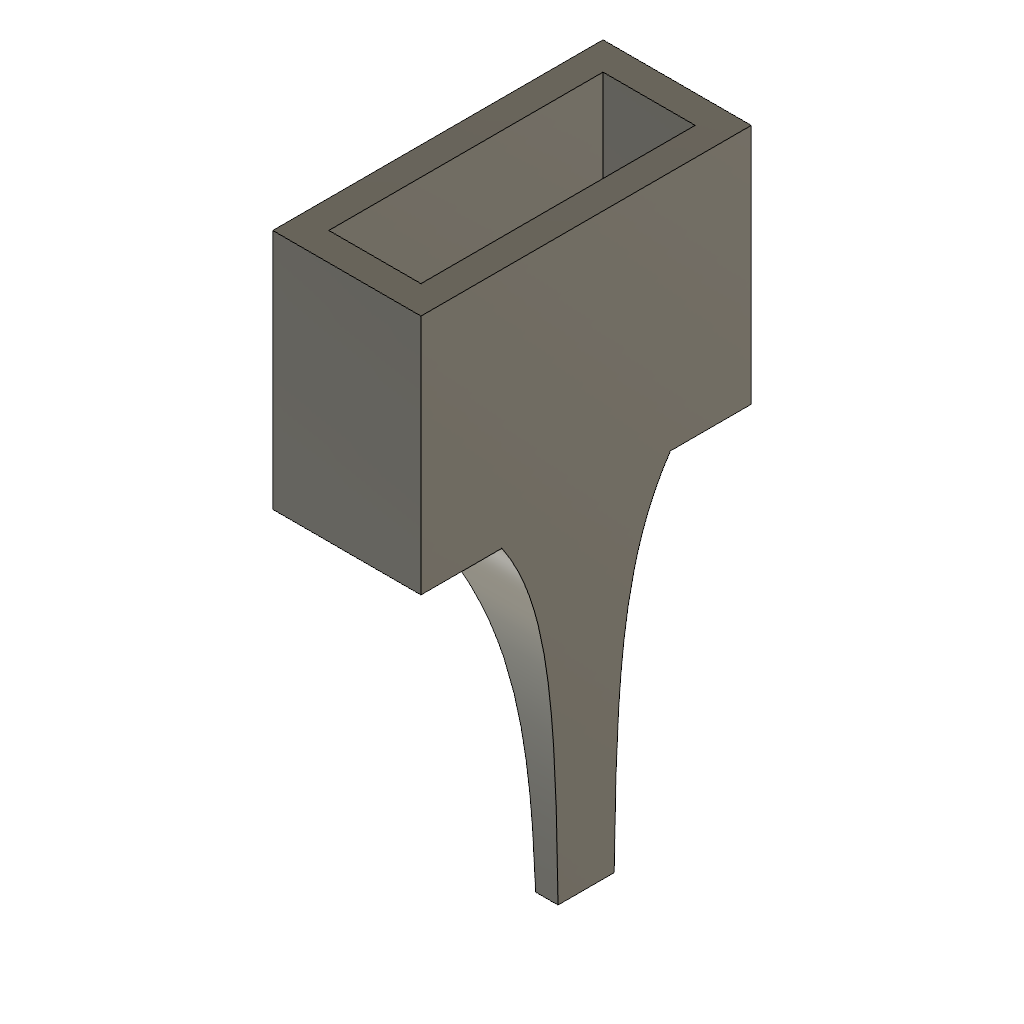
Gripper_R7_W15to5_L30_T2_C0p2 (Autodesk Fusion 360 design; units mm, degrees)
part number: 2026-10-26-02-16-46-155
Autodesk Fusion 360 part; units mm, degrees
sketch "01 - outside with 2.5 mm walls" plane through (0, 0, 0) normal (0, 0, 1) x (1, 0, 0)
  line L0 (-6.6, -14.7) -> (6.6, -14.7)
  line L1 (6.6, -14.7) -> (6.6, 14.7)
  line L2 (6.6, 14.7) -> (-6.6, 14.7)
  line L3 (-6.6, 14.7) -> (-6.6, -14.7)
  dimension "d12" = 13.2
  dimension "d13" = 29.4
  dimension "d14" = 6.6
  dimension "d15" = 14.7
  constraint horizontal L0
  constraint horizontal L2
  constraint vertical L1
  constraint vertical L3
  measures "d12" horizontal distance of L0.start L0.end
  measures "d13" vertical distance of L0.end L1.end
  measures "d14" horizontal distance of origin L0.start
  measures "d15" vertical distance of origin L0.start
extrude "02 - sleeve envelope with 2.5 mm closed base" add sketch "01 - outside with 2.5 mm walls" along normal blind 21.5
ref_plane "WorkPlane1" through (0, 0, 21.5) normal (0, 0, 1) x (1, 0, 0)
sketch "03 - finger pocket with fitting clearance" plane through (0, 0, 21.5) normal (0, 0, 1) x (1, 0, 0)
  line L0 (-4.1, -12.2) -> (4.1, -12.2)
  line L1 (4.1, -12.2) -> (4.1, 12.2)
  line L2 (4.1, 12.2) -> (-4.1, 12.2)
  line L3 (-4.1, 12.2) -> (-4.1, -12.2)
  dimension "d20" = 8.2
  dimension "d21" = 24.4
  dimension "d22" = 4.1
  dimension "d23" = 12.2
  constraint horizontal L0
  constraint horizontal L2
  constraint vertical L1
  constraint vertical L3
  measures "d20" horizontal distance of L0.start L0.end
  measures "d21" vertical distance of L0.end L1.end
  measures "d22" horizontal distance of origin L0.start
  measures "d23" vertical distance of origin L0.start
extrude "04 - open mouth and finger seating pocket" cut sketch "03 - finger pocket with fitting clearance" against normal blind 19
sketch "05 - exponential section 0" plane through (0, 0, 0) normal (0, 0, 1) x (1, 0, 0)
  line L0 (-6.6, -7.5) -> (6.6, -7.5)
  line L1 (6.6, -7.5) -> (6.6, 7.5)
  line L2 (6.6, 7.5) -> (-6.6, 7.5)
  line L3 (-6.6, 7.5) -> (-6.6, -7.5)
  dimension "d26" = 13.2
  dimension "d27" = 15
  dimension "d28" = 6.6
  dimension "d29" = 7.5
  constraint horizontal L0
  constraint horizontal L2
  constraint vertical L1
  constraint vertical L3
  measures "d26" horizontal distance of L0.start L0.end
  measures "d27" vertical distance of L0.end L1.end
  measures "d28" horizontal distance of origin L0.end
  measures "d29" vertical distance of origin L0.end
ref_plane "WorkPlane2" through (0, 0, -2.5) normal (0, 0, 1) x (1, 0, 0)
sketch "05 - exponential section 1" plane through (0, 0, -2.5) normal (0, 0, 1) x (1, 0, 0)
  line L0 (-3.3659, -6.0562) -> (6.6, -6.0562)
  line L1 (6.6, -6.0562) -> (6.6, 6.0562)
  line L2 (6.6, 6.0562) -> (-3.3659, 6.0562)
  line L3 (-3.3659, 6.0562) -> (-3.3659, -6.0562)
  dimension "d32" = 9.9659
  dimension "d33" = 12.1124
  dimension "d34" = 6.6
  dimension "d35" = 6.0562
  constraint horizontal L0
  constraint horizontal L2
  constraint vertical L1
  constraint vertical L3
  measures "d32" horizontal distance of L0.start L0.end
  measures "d33" vertical distance of L0.end L1.end
  measures "d34" horizontal distance of origin L0.end
  measures "d35" vertical distance of origin L0.end
ref_plane "WorkPlane3" through (0, 0, -5) normal (0, 0, 1) x (1, 0, 0)
sketch "05 - exponential section 2" plane through (0, 0, -5) normal (0, 0, 1) x (1, 0, 0)
  line L0 (-1.0486, -5.0217) -> (6.6, -5.0217)
  line L1 (6.6, -5.0217) -> (6.6, 5.0217)
  line L2 (6.6, 5.0217) -> (-1.0486, 5.0217)
  line L3 (-1.0486, 5.0217) -> (-1.0486, -5.0217)
  dimension "d38" = 7.6486
  dimension "d39" = 10.0434
  dimension "d40" = 6.6
  dimension "d41" = 5.0217
  constraint horizontal L0
  constraint horizontal L2
  constraint vertical L1
  constraint vertical L3
  measures "d38" horizontal distance of L0.start L0.end
  measures "d39" vertical distance of L0.end L1.end
  measures "d40" horizontal distance of origin L0.end
  measures "d41" vertical distance of origin L0.end
ref_plane "WorkPlane4" through (0, 0, -7.5) normal (0, 0, 1) x (1, 0, 0)
sketch "05 - exponential section 3" plane through (0, 0, -7.5) normal (0, 0, 1) x (1, 0, 0)
  line L0 (0.6118, -4.2804) -> (6.6, -4.2804)
  line L1 (6.6, -4.2804) -> (6.6, 4.2804)
  line L2 (6.6, 4.2804) -> (0.6118, 4.2804)
  line L3 (0.6118, 4.2804) -> (0.6118, -4.2804)
  dimension "d44" = 5.9882
  dimension "d45" = 8.5609
  dimension "d46" = 6.6
  dimension "d47" = 4.2804
  constraint horizontal L0
  constraint horizontal L2
  constraint vertical L1
  constraint vertical L3
  measures "d44" horizontal distance of L0.start L0.end
  measures "d45" vertical distance of L0.end L1.end
  measures "d46" horizontal distance of origin L0.end
  measures "d47" vertical distance of origin L0.end
ref_plane "WorkPlane5" through (0, 0, -10) normal (0, 0, 1) x (1, 0, 0)
sketch "05 - exponential section 4" plane through (0, 0, -10) normal (0, 0, 1) x (1, 0, 0)
  line L0 (1.8016, -3.7493) -> (6.6, -3.7493)
  line L1 (6.6, -3.7493) -> (6.6, 3.7493)
  line L2 (6.6, 3.7493) -> (1.8016, 3.7493)
  line L3 (1.8016, 3.7493) -> (1.8016, -3.7493)
  dimension "d50" = 4.7984
  dimension "d51" = 7.4986
  dimension "d52" = 6.6
  dimension "d53" = 3.7493
  constraint horizontal L0
  constraint horizontal L2
  constraint vertical L1
  constraint vertical L3
  measures "d50" horizontal distance of L0.start L0.end
  measures "d51" vertical distance of L0.end L1.end
  measures "d52" horizontal distance of origin L0.end
  measures "d53" vertical distance of origin L0.end
ref_plane "WorkPlane6" through (0, 0, -12.5) normal (0, 0, 1) x (1, 0, 0)
sketch "05 - exponential section 5" plane through (0, 0, -12.5) normal (0, 0, 1) x (1, 0, 0)
  line L0 (2.6541, -3.3687) -> (6.6, -3.3687)
  line L1 (6.6, -3.3687) -> (6.6, 3.3687)
  line L2 (6.6, 3.3687) -> (2.6541, 3.3687)
  line L3 (2.6541, 3.3687) -> (2.6541, -3.3687)
  dimension "d56" = 3.9459
  dimension "d57" = 6.7374
  dimension "d58" = 6.6
  dimension "d59" = 3.3687
  constraint horizontal L0
  constraint horizontal L2
  constraint vertical L1
  constraint vertical L3
  measures "d56" horizontal distance of L0.start L0.end
  measures "d57" vertical distance of L0.end L1.end
  measures "d58" horizontal distance of origin L0.end
  measures "d59" vertical distance of origin L0.end
ref_plane "WorkPlane7" through (0, 0, -15) normal (0, 0, 1) x (1, 0, 0)
sketch "05 - exponential section 6" plane through (0, 0, -15) normal (0, 0, 1) x (1, 0, 0)
  line L0 (3.2649, -3.096) -> (6.6, -3.096)
  line L1 (6.6, -3.096) -> (6.6, 3.096)
  line L2 (6.6, 3.096) -> (3.2649, 3.096)
  line L3 (3.2649, 3.096) -> (3.2649, -3.096)
  dimension "d62" = 3.3351
  dimension "d63" = 6.192
  dimension "d64" = 6.6
  dimension "d65" = 3.096
  constraint horizontal L0
  constraint horizontal L2
  constraint vertical L1
  constraint vertical L3
  measures "d62" horizontal distance of L0.start L0.end
  measures "d63" vertical distance of L0.end L1.end
  measures "d64" horizontal distance of origin L0.end
  measures "d65" vertical distance of origin L0.end
ref_plane "WorkPlane8" through (0, 0, -17.5) normal (0, 0, 1) x (1, 0, 0)
sketch "05 - exponential section 7" plane through (0, 0, -17.5) normal (0, 0, 1) x (1, 0, 0)
  line L0 (3.7026, -2.9006) -> (6.6, -2.9006)
  line L1 (6.6, -2.9006) -> (6.6, 2.9006)
  line L2 (6.6, 2.9006) -> (3.7026, 2.9006)
  line L3 (3.7026, 2.9006) -> (3.7026, -2.9006)
  dimension "d68" = 2.8974
  dimension "d69" = 5.8012
  dimension "d70" = 6.6
  dimension "d71" = 2.9006
  constraint horizontal L0
  constraint horizontal L2
  constraint vertical L1
  constraint vertical L3
  measures "d68" horizontal distance of L0.start L0.end
  measures "d69" vertical distance of L0.end L1.end
  measures "d70" horizontal distance of origin L0.end
  measures "d71" vertical distance of origin L0.end
ref_plane "WorkPlane9" through (0, 0, -20) normal (0, 0, 1) x (1, 0, 0)
sketch "05 - exponential section 8" plane through (0, 0, -20) normal (0, 0, 1) x (1, 0, 0)
  line L0 (4.0162, -2.7606) -> (6.6, -2.7606)
  line L1 (6.6, -2.7606) -> (6.6, 2.7606)
  line L2 (6.6, 2.7606) -> (4.0162, 2.7606)
  line L3 (4.0162, 2.7606) -> (4.0162, -2.7606)
  dimension "d74" = 2.5838
  dimension "d75" = 5.5212
  dimension "d76" = 6.6
  dimension "d77" = 2.7606
  constraint horizontal L0
  constraint horizontal L2
  constraint vertical L1
  constraint vertical L3
  measures "d74" horizontal distance of L0.start L0.end
  measures "d75" vertical distance of L0.end L1.end
  measures "d76" horizontal distance of origin L0.end
  measures "d77" vertical distance of origin L0.end
ref_plane "WorkPlane10" through (0, 0, -22.5) normal (0, 0, 1) x (1, 0, 0)
sketch "05 - exponential section 9" plane through (0, 0, -22.5) normal (0, 0, 1) x (1, 0, 0)
  line L0 (4.2409, -2.6603) -> (6.6, -2.6603)
  line L1 (6.6, -2.6603) -> (6.6, 2.6603)
  line L2 (6.6, 2.6603) -> (4.2409, 2.6603)
  line L3 (4.2409, 2.6603) -> (4.2409, -2.6603)
  dimension "d80" = 2.3591
  dimension "d81" = 5.3206
  dimension "d82" = 6.6
  dimension "d83" = 2.6603
  constraint horizontal L0
  constraint horizontal L2
  constraint vertical L1
  constraint vertical L3
  measures "d80" horizontal distance of L0.start L0.end
  measures "d81" vertical distance of L0.end L1.end
  measures "d82" horizontal distance of origin L0.end
  measures "d83" vertical distance of origin L0.end
ref_plane "WorkPlane11" through (0, 0, -25) normal (0, 0, 1) x (1, 0, 0)
sketch "05 - exponential section 10" plane through (0, 0, -25) normal (0, 0, 1) x (1, 0, 0)
  line L0 (4.402, -2.5884) -> (6.6, -2.5884)
  line L1 (6.6, -2.5884) -> (6.6, 2.5884)
  line L2 (6.6, 2.5884) -> (4.402, 2.5884)
  line L3 (4.402, 2.5884) -> (4.402, -2.5884)
  dimension "d86" = 2.198
  dimension "d87" = 5.1768
  dimension "d88" = 6.6
  dimension "d89" = 2.5884
  constraint horizontal L0
  constraint horizontal L2
  constraint vertical L1
  constraint vertical L3
  measures "d86" horizontal distance of L0.start L0.end
  measures "d87" vertical distance of L0.end L1.end
  measures "d88" horizontal distance of origin L0.end
  measures "d89" vertical distance of origin L0.end
ref_plane "WorkPlane12" through (0, 0, -27.5) normal (0, 0, 1) x (1, 0, 0)
sketch "05 - exponential section 11" plane through (0, 0, -27.5) normal (0, 0, 1) x (1, 0, 0)
  line L0 (4.5173, -2.5369) -> (6.6, -2.5369)
  line L1 (6.6, -2.5369) -> (6.6, 2.5369)
  line L2 (6.6, 2.5369) -> (4.5173, 2.5369)
  line L3 (4.5173, 2.5369) -> (4.5173, -2.5369)
  dimension "d92" = 2.0827
  dimension "d93" = 5.0738
  dimension "d94" = 6.6
  dimension "d95" = 2.5369
  constraint horizontal L0
  constraint horizontal L2
  constraint vertical L1
  constraint vertical L3
  measures "d92" horizontal distance of L0.start L0.end
  measures "d93" vertical distance of L0.end L1.end
  measures "d94" horizontal distance of origin L0.end
  measures "d95" vertical distance of origin L0.end
ref_plane "WorkPlane13" through (0, 0, -30) normal (0, 0, 1) x (1, 0, 0)
sketch "05 - exponential section 12" plane through (0, 0, -30) normal (0, 0, 1) x (1, 0, 0)
  line L0 (4.6, -2.5) -> (6.6, -2.5)
  line L1 (6.6, -2.5) -> (6.6, 2.5)
  line L2 (6.6, 2.5) -> (4.6, 2.5)
  line L3 (4.6, 2.5) -> (4.6, -2.5)
  dimension "d98" = 2
  dimension "d99" = 5
  dimension "d100" = 6.6
  dimension "d101" = 2.5
  constraint horizontal L0
  constraint horizontal L2
  constraint vertical L1
  constraint vertical L3
  measures "d98" horizontal distance of L0.start L0.end
  measures "d99" vertical distance of L0.end L1.end
  measures "d100" horizontal distance of origin L0.end
  measures "d101" vertical distance of origin L0.end
loft "06 - smooth exponential taper, aligned with +X sleeve wall" add profiles "05 - exponential section 0", "05 - exponential section 1", "05 - exponential section 2", "05 - exponential section 3", "05 - exponential section 4", "05 - exponential section 5", "05 - exponential section 6", "05 - exponential section 7", "05 - exponential section 8", "05 - exponential section 9", "05 - exponential section 10", "05 - exponential section 11", "05 - exponential section 12" section 1 section 2 section 3 section 4 section 5 section 6 section 7 section 8 section 9 section 10 section 11 section 12 section 13
equation "finger_width = 7.8 mm" comment "Measured finger width"
equation "finger_length = 24 mm" comment "Long edge of sleeve opening"
equation "finger_height = 19 mm" comment "Pocket depth along insertion axis"
equation "wall = 2.5 mm" comment "Sleeve side wall thickness"
equation "sleeve_height = finger_height + wall" comment "Pocket plus closed base thickness"
equation "blade_thickness = 2 mm" comment "Thickness at the gripping tip"
equation "blade_length = 30 mm" comment "Gripping finger length beyond the sleeve base"
equation "blade_width = 15 mm" comment "Gripping finger width at sleeve"
equation "blade_tip_width = 5 mm" comment "Gripping finger width at tip"
equation "fit_clearance = 0.2 mm" comment "ASSUMPTION: clearance on EACH side; test print to confirm fit"
equation "pocket_depth = finger_height" comment "Open recess depth to fit the existing finger"
equation "d12 = finger_width + 2 * fit_clearance + 2 * wall"
equation "d13 = finger_length + 2 * fit_clearance + 2 * wall"
equation "d14 = ( finger_width + 2 * fit_clearance + 2 * wall ) / 2"
equation "d15 = ( finger_length + 2 * fit_clearance + 2 * wall ) / 2"
equation "d16 = sleeve_height"
equation "d18 = sleeve_height"
equation "d20 = finger_width + 2 * fit_clearance"
equation "d21 = finger_length + 2 * fit_clearance"
equation "d22 = ( finger_width + 2 * fit_clearance ) / 2"
equation "d23 = ( finger_length + 2 * fit_clearance ) / 2"
equation "d24 = -( pocket_depth )"
equation "d26 = blade_thickness + ( ( finger_width + 2 * fit_clearance + 2 * wall ) - blade_thickness ) * 1.0"
equation "d27 = blade_tip_width + ( blade_width - blade_tip_width ) * 1.0"
equation "d28 = ( finger_width + 2 * fit_clearance + 2 * wall ) / 2"
equation "d29 = ( blade_tip_width + ( blade_width - blade_tip_width ) * 1.0 ) / 2"
equation "d30 = -blade_length * 0.08333333333333333"
equation "d32 = blade_thickness + ( ( finger_width + 2 * fit_clearance + 2 * wall ) - blade_thickness ) * 0.7112425330833178"
equation "d33 = blade_tip_width + ( blade_width - blade_tip_width ) * 0.7112425330833178"
equation "d34 = ( finger_width + 2 * fit_clearance + 2 * wall ) / 2"
equation "d35 = ( blade_tip_width + ( blade_width - blade_tip_width ) * 0.7112425330833178 ) / 2"
equation "d36 = -blade_length * 0.16666666666666666"
equation "d38 = blade_thickness + ( ( finger_width + 2 * fit_clearance + 2 * wall ) - blade_thickness ) * 0.5043387668755398"
equation "d39 = blade_tip_width + ( blade_width - blade_tip_width ) * 0.5043387668755398"
equation "d40 = ( finger_width + 2 * fit_clearance + 2 * wall ) / 2"
equation "d41 = ( blade_tip_width + ( blade_width - blade_tip_width ) * 0.5043387668755398 ) / 2"
equation "d42 = -blade_length * 0.25"
equation "d44 = blade_thickness + ( ( finger_width + 2 * fit_clearance + 2 * wall ) - blade_thickness ) * 0.3560857401120277"
equation "d45 = blade_tip_width + ( blade_width - blade_tip_width ) * 0.3560857401120277"
equation "d46 = ( finger_width + 2 * fit_clearance + 2 * wall ) / 2"
equation "d47 = ( blade_tip_width + ( blade_width - blade_tip_width ) * 0.3560857401120277 ) / 2"
equation "d48 = -blade_length * 0.3333333333333333"
equation "d50 = blade_thickness + ( ( finger_width + 2 * fit_clearance + 2 * wall ) - blade_thickness ) * 0.24985780454863735"
equation "d51 = blade_tip_width + ( blade_width - blade_tip_width ) * 0.24985780454863735"
equation "d52 = ( finger_width + 2 * fit_clearance + 2 * wall ) / 2"
equation "d53 = ( blade_tip_width + ( blade_width - blade_tip_width ) * 0.24985780454863735 ) / 2"
equation "d54 = -blade_length * 0.4166666666666667"
equation "d56 = blade_thickness + ( ( finger_width + 2 * fit_clearance + 2 * wall ) - blade_thickness ) * 0.17374216265985326"
equation "d57 = blade_tip_width + ( blade_width - blade_tip_width ) * 0.17374216265985326"
equation "d58 = ( finger_width + 2 * fit_clearance + 2 * wall ) / 2"
equation "d59 = ( blade_tip_width + ( blade_width - blade_tip_width ) * 0.17374216265985326 ) / 2"
equation "d60 = -blade_length * 0.5"
equation "d62 = blade_thickness + ( ( finger_width + 2 * fit_clearance + 2 * wall ) - blade_thickness ) * 0.11920292202211756"
equation "d63 = blade_tip_width + ( blade_width - blade_tip_width ) * 0.11920292202211756"
equation "d64 = ( finger_width + 2 * fit_clearance + 2 * wall ) / 2"
equation "d65 = ( blade_tip_width + ( blade_width - blade_tip_width ) * 0.11920292202211756 ) / 2"
equation "d66 = -blade_length * 0.5833333333333334"
equation "d68 = blade_thickness + ( ( finger_width + 2 * fit_clearance + 2 * wall ) - blade_thickness ) * 0.08012384845026153"
equation "d69 = blade_tip_width + ( blade_width - blade_tip_width ) * 0.08012384845026153"
equation "d70 = ( finger_width + 2 * fit_clearance + 2 * wall ) / 2"
equation "d71 = ( blade_tip_width + ( blade_width - blade_tip_width ) * 0.08012384845026153 ) / 2"
equation "d72 = -blade_length * 0.6666666666666666"
equation "d74 = blade_thickness + ( ( finger_width + 2 * fit_clearance + 2 * wall ) - blade_thickness ) * 0.052122468647810026"
equation "d75 = blade_tip_width + ( blade_width - blade_tip_width ) * 0.052122468647810026"
equation "d76 = ( finger_width + 2 * fit_clearance + 2 * wall ) / 2"
equation "d77 = ( blade_tip_width + ( blade_width - blade_tip_width ) * 0.052122468647810026 ) / 2"
equation "d78 = -blade_length * 0.75"
equation "d80 = blade_thickness + ( ( finger_width + 2 * fit_clearance + 2 * wall ) - blade_thickness ) * 0.032058603280084995"
equation "d81 = blade_tip_width + ( blade_width - blade_tip_width ) * 0.032058603280084995"
equation "d82 = ( finger_width + 2 * fit_clearance + 2 * wall ) / 2"
equation "d83 = ( blade_tip_width + ( blade_width - blade_tip_width ) * 0.032058603280084995 ) / 2"
equation "d84 = -blade_length * 0.8333333333333334"
equation "d86 = blade_thickness + ( ( finger_width + 2 * fit_clearance + 2 * wall ) - blade_thickness ) * 0.017682215532972913"
equation "d87 = blade_tip_width + ( blade_width - blade_tip_width ) * 0.017682215532972913"
equation "d88 = ( finger_width + 2 * fit_clearance + 2 * wall ) / 2"
equation "d89 = ( blade_tip_width + ( blade_width - blade_tip_width ) * 0.017682215532972913 ) / 2"
equation "d90 = -blade_length * 0.9166666666666666"
equation "d92 = blade_thickness + ( ( finger_width + 2 * fit_clearance + 2 * wall ) - blade_thickness ) * 0.007381083579217742"
equation "d93 = blade_tip_width + ( blade_width - blade_tip_width ) * 0.007381083579217742"
equation "d94 = ( finger_width + 2 * fit_clearance + 2 * wall ) / 2"
equation "d95 = ( blade_tip_width + ( blade_width - blade_tip_width ) * 0.007381083579217742 ) / 2"
equation "d96 = -blade_length * 1.0"
equation "d98 = blade_thickness + ( ( finger_width + 2 * fit_clearance + 2 * wall ) - blade_thickness ) * 0.0"
equation "d99 = blade_tip_width + ( blade_width - blade_tip_width ) * 0.0"
equation "d100 = ( finger_width + 2 * fit_clearance + 2 * wall ) / 2"
equation "d101 = ( blade_tip_width + ( blade_width - blade_tip_width ) * 0.0 ) / 2"
named bodies: "Sleeve and integral gripping finger"
